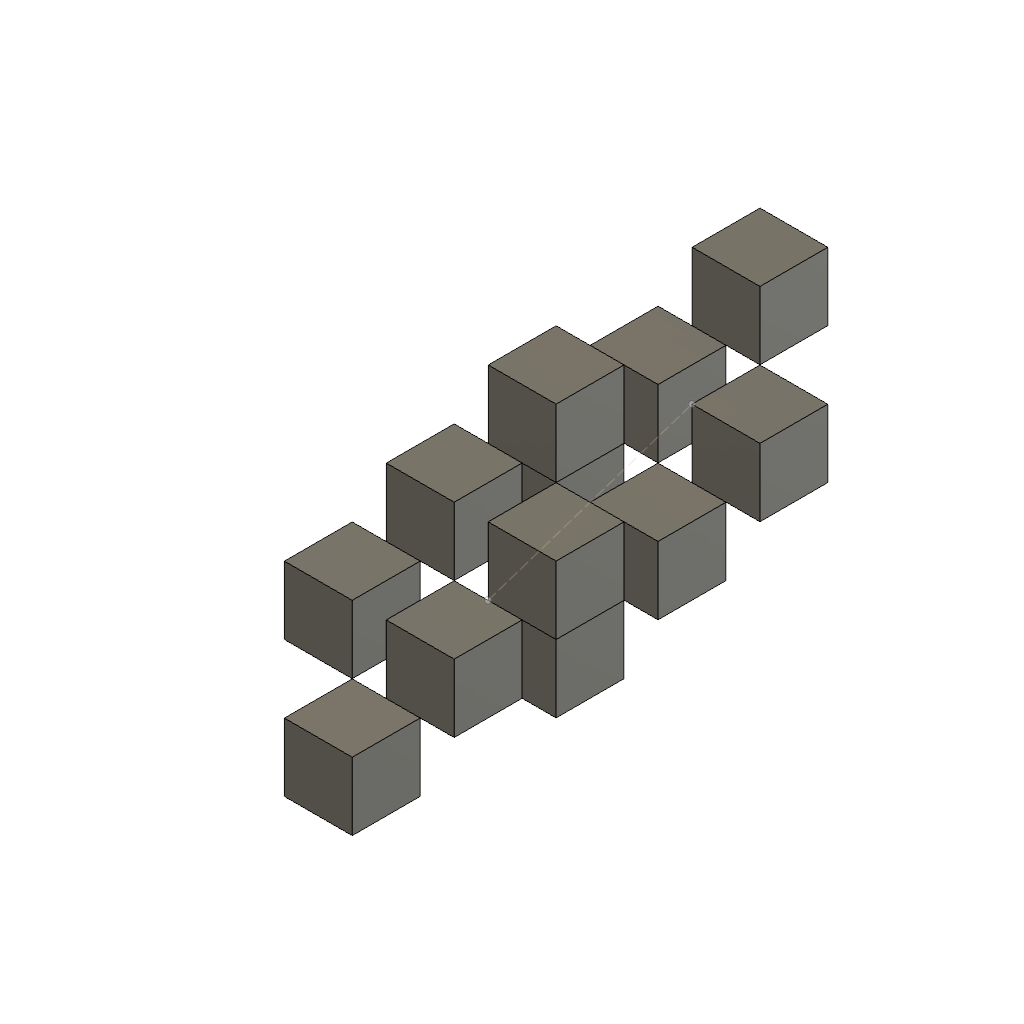
body_multiple_customaxis (Autodesk Fusion 360 design; units mm, degrees)
part number: 2026-10-20-21-45-06-322
Autodesk Fusion 360 part; units mm, degrees
sketch "Sketch1" plane through (0, 0, 0) normal (0, 0, 1) x (1, 0, 0)
  line L0 (10, 0) -> (20, 0)
  line L1 (20, 0) -> (20, 10)
  line L2 (20, 10) -> (10, 10)
  line L3 (10, 10) -> (10, 0)
extrude "SeedFeature0" add sketch "Sketch1" along normal blind 10 makes body 1
sketch "Sketch2" plane through (0, 0, 0) normal (0, 0, 1) x (1, 0, 0)
  line L0 (10, 20) -> (20, 20)
  line L1 (20, 20) -> (20, 30)
  line L2 (20, 30) -> (10, 30)
  line L3 (10, 30) -> (10, 20)
extrude "SeedFeature1" add sketch "Sketch2" along normal blind 10 separate body makes body 2
sketch "PatternDirections" plane through (0, 0, 0) normal (0, 0, 1) x (1, 0, 0)
  line L0 (0, 0) -> (30, 40) construction
pattern_linear "ProbeRectangularPattern" count 3 spacing 25 along (0.6, 0.8, 0) count 2 spacing 30 along (0, 0, 1) of bodies 1 2 makes body 3 at (25, 26.6667, 3.3333) makes body 4 at (40, 46.6667, 3.3333) makes body 5 at (10, 6.6667, 33.3333) makes body 6 at (25, 26.6667, 33.3333) makes body 7 at (40, 46.6667, 33.3333) makes body 8 at (25, 46.6667, 3.3333) makes body 9 at (40, 66.6667, 3.3333) makes body 10 at (10, 26.6667, 33.3333) makes body 11 at (25, 46.6667, 33.3333) makes body 12 at (40, 66.6667, 33.3333)
named bodies: "SeedBody0", "SeedBody1", "SeedBody0 (1)", "SeedBody0 (2)", "SeedBody0 (3)", "SeedBody0 (4)", "SeedBody0 (5)", "SeedBody1 (1)", "SeedBody1 (2)", "SeedBody1 (3)", "SeedBody1 (4)", "SeedBody1 (5)"
